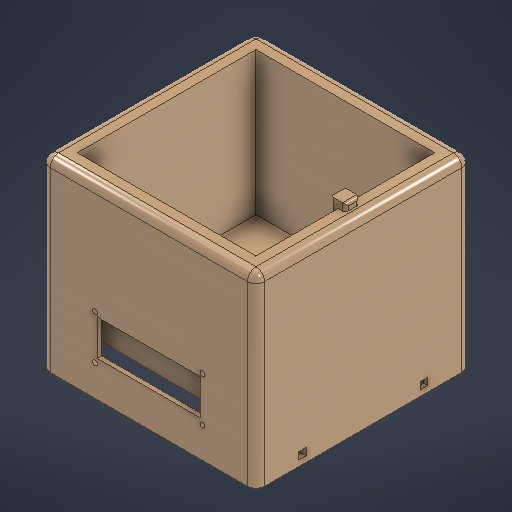
# Autodesk Inventor part: Caixa Principal
Saved by Autodesk Inventor 2027.1 (Build 311270010, 270A)
## iProperties
Created: 2026-07-28
Part Number: Caixa Principal
Material: Genérico
Document SubType Name: Modeling
Designer: enric
Density: 1 g/cm^3
Appearance: Rajado
Author: enric
Autodesk Inventor part; units mm, degrees
ref_plane "YZ Plane" through (0, 0, 0) normal (1, 0, 0) x (0, 1, 0)
ref_plane "XZ Plane" through (0, 0, 0) normal (0, 1, 0) x (-1, 0, 0)
ref_plane "XY Plane" through (0, 0, 0) normal (0, 0, 1) x (1, 0, 0)
sketch "Esboço1" plane through (0, 0, 0) normal (0, 1, 0) x (-1, 0, 0)
  line L0 (-75, 75) -> (75, 75)
  line L1 (75, 75) -> (75, -75)
  line L2 (75, -75) -> (-75, -75)
  line L3 (-75, -75) -> (-75, 75)
  line L4 (-75, 75) -> (75, -75) construction
  line L5 (75, 75) -> (-75, -75) construction
  point P0 (0, 0)
  dimension "d0" = 150
  dimension "d1" = 150
  constraints: 12 end point, 2 midpoint, 2 parallel, 1 horizontal, 1 perpendicular
  measures "d0" distance of L1.end L2.end
  measures "d1" distance of L0.end L1.end
extrude "Extrusão1" add sketch "Esboço1" along normal blind 130
sketch "Esboço2" plane through (0, 130, 0) normal (0, 1, 0) x (1, 0, 0)
  line L0 (-75, 75) -> (-75, -75) projected
  line L1 (75, 75) -> (-75, 75) projected
  line L2 (-75, -75) -> (75, -75) projected
  line L3 (75, -75) -> (75, 75) projected
  line L4 (62.5, -62.5) -> (-62.5, -62.5)
  line L5 (-62.5, -62.5) -> (-62.5, 62.5)
  line L6 (-62.5, 62.5) -> (62.5, 62.5)
  line L7 (62.5, 62.5) -> (62.5, -62.5)
  line L8 (62.5, -62.5) -> (-62.5, 62.5) construction
  line L9 (-62.5, -62.5) -> (62.5, 62.5) construction
  point P0 (0, 0)
  dimension "d4" = 125
  dimension "d5" = 125
  dimension "d20" = 150
  constraints: 12 end point, 2 midpoint, 2 parallel, 1 horizontal, 1 perpendicular
  measures "d4" distance of L5.end L6.end
  measures "d5" distance of L4.end L5.end
  measures "d20" distance of L1.start L0.start
extrude "Extrusão2" cut sketch "Esboço2" against normal blind 100 contours L4 L5 L6 L7
shell "Casca1" thickness 3 removed faces 1 at (25, 0, 25)
sketch "Esboço3" plane through (-75, 0, 75) normal (0, 0, 1) x (1, 0, 0)
  line L0 (75, 0) -> (75, 25) construction
  line L1 (39, 25) -> (111, 25)
  line L2 (39, 25) -> (39, 50)
  line L3 (39, 50) -> (111, 50)
  line L4 (111, 50) -> (111, 25)
  line L5 (75, 50) -> (75, 52.5) construction
  line L6 (37.5, 52.5) -> (112.5, 52.5) construction
  circle A0 centre (112.5, 52.5) radius 1.75
  circle A1 centre (37.5, 52.5) radius 1.75
  line L7 (112.5, 52.5) -> (112.5, 21.5) construction
  line L8 (12.5, 30) -> (137.5, 30) construction
  line L9 (112.5, 52.5) -> (143.5, 52.5) construction
  circle A2 centre (112.5, 21.5) radius 1.75
  line L10 (112.5, 21.5) -> (37.5, 21.5) construction
  circle A3 centre (37.5, 21.5) radius 1.75
  line L11 (37.5, 52.5) -> (37.5, 21.5) construction
  dimension "d9" = 25
  dimension "d10" = 72
  dimension "d11" = 25
  dimension "d12" = 2.5
  dimension "d13" = 75
  dimension "d14" = 3.5
  dimension "d15" = 3.5
  dimension "d16" = 31
  dimension "d17" = 90
  dimension "d18" = 3.5
  dimension "d19" = 3.5
  constraints: 22 end point, 5 horizontal, 4 centre point, 4 coincident, 4 vertical, 3 midpoint, 3 perpendicular
  measures "d9" distance of L0.start L0.end
  measures "d10" distance of L1.start L1.end
  measures "d11" distance of L1.start L2.end
  measures "d12" distance of L5.start L5.end
  measures "d13" distance of L6.start L6.end
  measures "d14" diameter of A0
  measures "d15" diameter of A1
  measures "d16" distance of L7.start L7.end
  measures "d17" angle of L7 L9
  measures "d18" diameter of A2
  measures "d19" diameter of A3
extrude "Extrusão3" cut sketch "Esboço3" against normal blind 5 contours A0 | A1 | A2 | A3
extrude "Extrusão4" cut sketch "Esboço3" against normal blind 5 contours L2 L3 L4 L1
fillet "Arredondamento4" radius 6 8 edges at (-75, 65, 75) (0, 130, 75) (-75, 130, 0) (-75, 65, -75) (0, 130, -75) (75, 65, -75) (75, 130, 0) (75, 65, 75)
sketch "Esboço4" plane through (62.5, 130, -62.5) normal (-1, 0, 0) x (0, 0, 1)
  line L0 (-3, -3) -> (128, -3) projected
  line L1 (128, -3) -> (128, -103) projected
  line L2 (-3, -103) -> (128, -103) projected
  line L3 (-3, -3) -> (-3, -103) projected
  line L4 (-3, -3) -> (128, -3) projected
  line L5 (67.5, -3) -> (57.5, -3)
  line L6 (57.5, -3) -> (57.5, -33)
  line L7 (67.5, -3) -> (67.5, -33)
  line L8 (57.5, -3) -> (57.5, 5)
  line L9 (67.5, -3) -> (67.5, 5)
  line L10 (-6.5, 0) -> (131.5, 0) projected
  line L11 (57.5, 5) -> (67.5, 5)
  line L12 (57.5, -33) -> (67.5, -33)
  point P0 (62.5, -130)
  point P1 (62.5, -3)
  dimension "d29" = 10
  dimension "d30" = 30
  dimension "d31" = 8
  dimension "d32" = 8
  constraints: 14 end point, 2 midpoint, 2 perpendicular, 2 point on line, 1 horizontal, 1 vertical
  measures "d29" distance of L5.start L5.end
  measures "d30" distance of L5.end L6.end
  measures "d31" distance of L5.end L8.end
  measures "d32" distance of L5.start L9.end
extrude "Extrusão5" add sketch "Esboço4" along normal blind 5 contours L8 L10 L9 L0 | L0 L7 L12 L6 | L8 L11 L9 L10
fillet "Arredondamento5" radius 2 2 edges at (57.5, 116, 5) (57.5, 116, -5)
sketch "Esboço5" plane through (62.5, 130, -62.5) normal (1, 0, 0) x (0, 0, -1)
  line L0 (-125, 0) -> (0, 0) projected
  line L1 (-65.5, 5) -> (-59.5, 5) projected
  line L2 (-66.5, 0) -> (-58.5, 0)
  line L3 (-66.5, 0) -> (-66.5, 3)
  line L4 (-66.5, 3) -> (-58.5, 3)
  line L5 (-59.5, -33) -> (-59.5, 5) construction
  line L6 (-58.5, 3) -> (-58.5, 0)
  point P0 (-62.5, -130)
  point P1 (-62.5, 0)
  dimension "d36" = 8
  dimension "d37" = 3
  constraints: 8 end point, 3 perpendicular, 2 midpoint, 1 point on line
  measures "d36" distance of L2.start L2.end
  measures "d37" distance of L2.start L3.end
extrude "Extrusão6" cut sketch "Esboço5" against normal blind 4
sketch "Esboço6" plane through (0, 130, 0) normal (0, 1, 0) x (1, 0, 0)
  line L0 (62.5, -5) -> (62.5, 5) projected
  line L1 (62.5, 4) -> (58.5, 4) projected
  line L2 (58.5, 4) -> (58.5, -4) projected
  line L3 (62.5, -4) -> (58.5, -4) projected
  line L4 (58.5, -4) -> (62.5, -4)
  line L5 (62.5, -4) -> (62.5, 4)
  line L6 (62.5, 4) -> (58.5, 4)
  line L7 (58.5, 4) -> (58.5, -4)
  point P0 (0, 0)
  constraints: 8 end point, 2 parallel, 1 horizontal, 1 perpendicular
extrude "Extrusão7" cut sketch "Esboço6" against normal blind 50
sketch "Esboço7" plane through (0, 130, 0) normal (0, 1, 0) x (1, 0, 0)
  line L0 (62.5, 5) -> (59.5, 5) projected
  line L1 (62.5, -5) -> (59.5, -5) projected
  line L2 (57.5, 3) -> (57.5, -3) projected
  line L3 (62.5, 4) -> (62.5, 5) projected
  line L4 (62.5, 5) -> (67.5, 5)
  line L5 (62.5, -5) -> (62.5, 5)
  line L6 (62.5, 62.5) -> (62.5, -62.5) projected
  line L7 (67.5, 5) -> (67.5, -5)
  line L8 (67.5, -5) -> (62.5, -5)
  line L9 (62.5, 0) -> (64, 0) construction
  line L10 (64, 4) -> (66.5, 4)
  line L11 (64, -4) -> (66.5, -4)
  line L12 (66.5, -4) -> (66.5, 4)
  line L13 (65.25, 4) -> (65.25, 5) construction
  line L14 (62.5, 4) -> (64, 4)
  line L15 (64, -4) -> (62.5, -4)
  line L16 (64, 0) -> (64, 4)
  line L17 (64, 0) -> (64, -4)
  point P0 (0, 0)
  dimension "d42" = 5
  dimension "d43" = 1.5
  dimension "d44" = 2.5
  constraints: 26 end point, 4 horizontal, 4 perpendicular, 3 vertical, 2 collinear, 2 midpoint, 2 point on line
  measures "d42" distance of L0.start L4.end
  measures "d43" distance of L9.start L9.end
  measures "d44" distance of L10.start L10.end
extrude "Extrusão8" cut sketch "Esboço7" against normal blind 15 contours L10 L12 L11 L17 L16
extrude "Extrusão9" add sketch "Esboço7" along normal blind 5 contours L3 L4 L7 L8 L5 L15 L11 L12 L10 L14
sketch "Esboço9" plane through (62.5, 130, -62.5) normal (1, 0, 0) x (0, 0, -1)
  line L0 (-67.5, 5) -> (-65.5, 5) projected
  line L1 (-58.5, 3) -> (-58.5, -33) projected
  line L2 (-66.5, 5) -> (-58.5, 5)
  line L3 (-58.5, 5) -> (-58.5, 3)
  line L4 (-58.5, 3) -> (-66.5, 3)
  line L5 (-66.5, 3) -> (-66.5, 5)
  point P0 (-62.5, -130)
  constraints: 8 end point, 2 parallel, 1 horizontal, 1 midpoint, 1 perpendicular
extrude "Extrusão10" add sketch "Esboço9" along normal blind 4
fillet "Arredondamento6" radius 2 3 edges at (67.5, 132.5, 5) (67.5, 135, 0) (67.5, 132.5, -5)
sketch "Esboço10" plane through (75, 0, 69) normal (1, 0, 0) x (0, 0, -1)
  line L0 (69, 0) -> (69, 146.3612)
  line L1 (0, 0) -> (138, 0) projected
  line L2 (69, 0) -> (69, 4) construction
  line L3 (26.5, 4) -> (111.5, 4) construction
  line L4 (109, 4) -> (114, 4)
  line L5 (24, 4) -> (29, 4)
  line L6 (24, 4) -> (24, 9)
  line L7 (24, 9) -> (29, 9)
  line L8 (29, 9) -> (29, 4)
  line L9 (109, 4) -> (109, 9)
  line L10 (109, 9) -> (114, 9)
  line L11 (114, 9) -> (114, 4)
  dimension "d52" = 4
  dimension "d56" = 85
  dimension "d57" = 5
  dimension "d62" = 5
  dimension "d63" = 5
  dimension "d64" = 5
  dimension "d65" = 5
  dimension "d66" = 5
  constraints: 22 end point, 3 midpoint, 3 vertical, 2 perpendicular, 2 point on line, 1 horizontal, 1 parallel
  measures "d52" distance of L0.start L2.end
  measures "d56" distance of L3.start L3.end
  measures "d57" distance of L4.start L4.end
  measures "d62" distance of L5.start L5.end
  measures "d63" distance of L5.start L6.end
  measures "d64" distance of L6.end L7.end
  measures "d65" distance of L4.start L9.end
  measures "d66" distance of L9.end L10.end
extrude "Extrusão11" cut sketch "Esboço10" against normal blind 10
sketch "Esboço11" plane through (-75, 0, -69) normal (-1, 0, 0) x (0, 0, 1)
  line L0 (0, 0) -> (138, 0) projected
  line L1 (69, 0) -> (69, 151.3917)
  line L2 (69, 0) -> (69, 4) construction
  line L3 (26.5, 4) -> (111.5, 4) construction
  line L4 (114, 4) -> (109, 4) projected
  line L5 (109, 4) -> (114, 4)
  line L6 (109, 4) -> (109, 9)
  line L7 (109, 9) -> (114, 9)
  line L8 (114, 9) -> (114, 4)
  line L9 (29, 4) -> (24, 4) projected
  line L10 (29, 4) -> (24, 4)
  line L11 (24, 4) -> (24, 9)
  line L12 (24, 9) -> (29, 9)
  line L13 (29, 9) -> (29, 4)
  dimension "d69" = 4
  dimension "d70" = 85
  dimension "d71" = 5
  dimension "d72" = 5
  dimension "d73" = 5
  dimension "d74" = 5
  dimension "d75" = 5
  constraints: 22 end point, 3 midpoint, 3 perpendicular, 3 vertical, 1 horizontal, 1 point on line
  measures "d69" distance of L1.start L2.end
  measures "d70" distance of L3.start L3.end
  measures "d71" distance of L5.start L4.start
  measures "d72" distance of L5.start L6.end
  measures "d73" distance of L10.start L9.end
  measures "d74" distance of L9.end L11.end
  measures "d75" distance of L11.end L12.end
extrude "Extrusão12" cut sketch "Esboço11" against normal blind 10
sketch "Esboço12" plane through (69, 0, -75) normal (0, 0, -1) x (-1, 0, 0)
  line L0 (-3, 0) -> (141, 0) projected
  line L1 (69, 0) -> (69, 15) construction
  circle A0 centre (69, 15) radius 5
  dimension "d78" = 15
  dimension "d79" = 10
  constraints: 2 end point, 1 centre point, 1 coincident, 1 vertical
  measures "d78" distance of L1.start L1.end
  measures "d79" diameter of A0
extrude "Extrusão13" cut sketch "Esboço12" against normal blind 10
